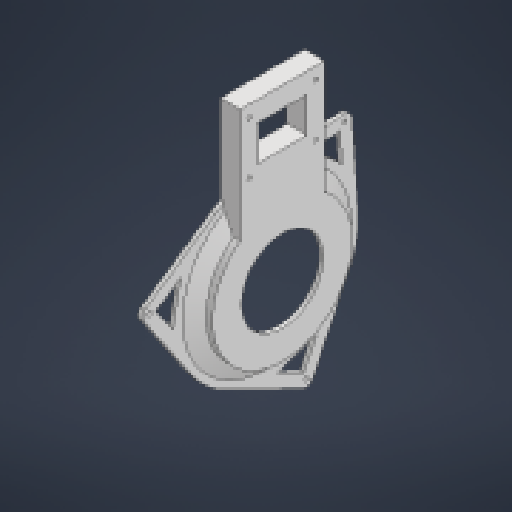
# Autodesk Inventor part: GearCover
Saved by Autodesk Inventor 2027.1 (Build 311270010, 270A)
## iProperties
Created: 2026-11-11
Part Number: GearCover
Material: 一般
Document SubType Name: Modeling
Designer: takuya
Density: 1 g/cm^3
Appearance: 既定
Author: takuya
Autodesk Inventor part; units mm, degrees
ref_plane "作業平面1" through (-57.527, 0, 0) normal (0, 0, 1) x (1, 0, 0)
sketch "スケッチ1" plane through (-57.527, 0, 0) normal (0, 0, 1) x (1, 0, 0)
  line L0 (49.9135, 26.8347) -> (49.9135, 126.8347) projected
  line L1 (35.6909, 64.8149) -> (35.6909, 53.8072) projected
  line L2 (45.137, 49.6849) -> (35.6909, 64.8149)
  line L3 (49.9135, 29.1608) -> (46.9135, 29.1608)
  line L4 (46.9135, 29.1608) -> (35.6909, 53.8072)
  line L5 (49.9135, 29.1608) -> (45.137, 49.6849)
  line L6 (31.3237, 0) -> (61.8943, 0) projected
  point P0 (57.527, 0)
  dimension "d0" = 3
  constraints: 8 end point, 1 horizontal, 1 point on line
  measures "d0" distance of L3.start L3.end
revolve "回転1" add sketch "スケッチ1" angle 360 about axis through (-10, 0, 0) along (1, 0, 0)
sketch "スケッチ2" plane through (-21.8361, 0, 0) normal (-1, 0, 0) x (0, 0, 1)
  line L0 (-32.4955, -82.426) -> (-58.582, -28.1628) projected
  line L1 (-35.518, -56.4528) -> (-26.3428, -75.5385) projected
  arc A0 (-32.4955, -82.426) -> (-25.8072, -84.7584) centre (-27.9892, -80.2596) ccw projected
  circle A1 centre (-27.9892, -80.2596) radius 1.5 projected
  line L2 (-7.2889, -66.2972) -> (-35.518, -56.4528) projected
  line L3 (-26.3428, -75.5385) -> (-7.2889, -66.2972) projected
  line L4 (28.3654, -58.4842) -> (-25.8072, -84.7584) projected
  line L5 (-64.8315, 4.677) -> (-60.4993, 64.7289) projected
  arc A2 (-55.1353, 69.3549) -> (-60.4993, 64.7289) centre (-55.5123, 64.3691) ccw projected
  circle A3 centre (-55.5123, 64.3691) radius 1.5 projected
  line L6 (-52.2469, 60.5827) -> (-53.7706, 39.461) projected
  line L7 (-53.7706, 39.461) -> (-31.1305, 58.9859) projected
  line L8 (-31.1305, 58.9859) -> (-52.2469, 60.5827) projected
  line L9 (-55.1353, 69.3549) -> (4.9013, 64.8149) projected
  line L10 (78.5896, 14.9557) -> (61.0595, 26.8362) projected
  line L11 (66.6486, -2.5331) -> (78.5896, 14.9557) projected
  line L12 (61.0595, 26.8362) -> (66.6486, -2.5331) projected
  circle A4 centre (83.5015, 15.8905) radius 1.5 projected
  arc A5 (87.6307, 13.0711) -> (86.3065, 20.0295) centre (83.5015, 15.8905) ccw projected
  line L13 (36.4662, 53.8072) -> (86.3065, 20.0295) projected
  line L14 (87.6307, 13.0711) -> (53.6807, -36.6521) projected
  arc A6 (-64.8315, 4.677) -> (-58.582, -28.1628) centre (0, 0) ccw projected
  arc A7 (36.4662, 53.8072) -> (4.9013, 64.8149) centre (0, 0) ccw projected
  arc A8 (28.3654, -58.4842) -> (53.6807, -36.6521) centre (0, 0) ccw projected
  circle A9 centre (0, 0) radius 64.8149 projected
  circle A10 centre (0, 0) radius 60
  point P0 (0, 0)
  dimension "d2" = 120
  constraints: 1 centre point, 1 coincident
  measures "d2" diameter of A10
extrude "押し出し1" add sketch "スケッチ2" against normal blind 3 contours L0 A6 L5 A2 L9 A7 L13 A5 L14 A8 L4 A0 | A9
ref_plane "作業平面3" through (-8.0199, 25.6061, 28.2776) normal (-0.0101, -0.0315, 0.9995) x (0.9999, -0.0002, 0.0101)
ref_plane "作業平面4" through (-7.6135, 80.3865, 20) normal (-1, 0, 0) x (0, 0, 1)
sketch "スケッチ6" plane through (-7.6135, 80.3865, 20) normal (-1, 0, 0) x (0, 0, 1)
  circle A0 centre (-43.5, 31.5) radius 1.5 projected
  circle A1 centre (-43.5, -5.5) radius 1.5 projected
  line L0 (-40, 47) -> (-40, 50) projected
  line L1 (-40, 50) -> (-50, 50) projected
  line L2 (-50, -50) -> (-50, 50) projected
  line L3 (-40, -50) -> (-50, -50) projected
  line L4 (-40, -50) -> (-40, -47) projected
  line L5 (-40, -47) -> (-33, -47) projected
  line L6 (-33, -47) -> (-33, -40) projected
  line L7 (-33, -40) -> (-40, -40) projected
  line L8 (-40, -40) -> (-40, 40) projected
  line L9 (-40, 40) -> (-33, 40) projected
  line L10 (-33, 40) -> (-33, 47) projected
  line L11 (-33, 47) -> (-40, 47) projected
  circle A2 centre (3.5, 31.5) radius 1.5 projected
  circle A3 centre (3.5, -5.5) radius 1.5 projected
  line L12 (0, 47) -> (0, 50) projected
  line L13 (-7, 47) -> (0, 47) projected
  line L14 (-7, 40) -> (-7, 47) projected
  line L15 (0, 40) -> (-7, 40) projected
  line L16 (0, -40) -> (0, 40) projected
  line L17 (-7, -40) -> (0, -40) projected
  line L18 (-7, -47) -> (-7, -40) projected
  line L19 (0, -47) -> (-7, -47) projected
  line L20 (0, -50) -> (0, -47) projected
  line L21 (0, -50) -> (10, -50) projected
  line L22 (10, -50) -> (10, 50) projected
  line L23 (0, 50) -> (10, 50) projected
  line L24 (-40, -47) -> (10, -47)
  line L25 (0, 40) -> (-50, 40)
  line L26 (10, -47) -> (-50, -47)
  line L27 (-50, -47) -> (-50, 40)
  line L28 (-50, 40) -> (10, 40)
  line L29 (10, 40) -> (10, -47)
  point P0 (-20, -80.3865)
  point P1 (-7, -47)
  point P2 (0, -47)
  point P3 (10, 40)
  point P4 (0, 40)
  point P5 (-7, 40)
  point P6 (-33, 40)
  point P7 (-40, 40)
  point P8 (-50, -47)
  point P9 (-40, -47)
  point P10 (-33, -47)
  constraints: 12 end point, 3 perpendicular, 2 parallel, 2 point on line, 1 horizontal
extrude "押し出し3" add sketch "スケッチ6" along normal up to surface (14.2226 mm away) contours L25 L15 L16 L17 L18 L24 L6 L7 L8 L9 | L25 L8 L7 L6 L5 L26 L2 | L28 L22 L24 L19 L18 L17 L16
sketch "スケッチ7" plane through (-57.527, 0, 0) normal (0, 0, 1) x (1, 0, 0)
  line L0 (46.9135, -29.1608) -> (35.6909, -53.8072) projected
  line L1 (35.6909, 44.6679) -> (35.6909, 44.6679) projected
  line L2 (46.9135, -29.1608) -> (46.9135, 29.1608) projected
  line L3 (35.6909, -53.8072) -> (35.6909, 44.6679) projected
  line L4 (46.9135, 0) -> (35.6909, 0)
  line L5 (35.6909, 0) -> (35.6909, -53.8072)
  line L6 (35.6909, -53.8072) -> (46.9135, -53.8072)
  line L7 (46.9135, -53.8072) -> (46.9135, 0)
  line L8 (31.2731, 0) -> (61.9027, 0) projected
  point P0 (57.527, 0)
  point P1 (39.7536, 33.3865)
  point P2 (39.7536, 33.3865)
  constraints: 8 end point, 2 parallel, 1 horizontal, 1 midpoint, 1 perpendicular, 1 vertical alignment, 2 other
revolve "回転2" cut sketch "スケッチ7" angle 360 about axis through (-10, 0, 0) along (1, 0, 0) contours L0 L3 L4 L2
sketch "スケッチ8" plane through (-57.527, 0, 0) normal (0, 0, 1) x (1, 0, 0)
  line L0 (49.9135, 33.3865) -> (46.2541, 33.3865) projected
  line L1 (49.9135, -126.3888) -> (49.9135, 161.5157) projected
  line L2 (46.9135, -29.1608) -> (46.9135, 29.1608) projected
  line L3 (46.9135, 29.1608) -> (46.2541, 33.3865)
  line L4 (49.9135, 29.1608) -> (46.9135, 29.1608) projected
  line L5 (48.9301, 33.3865) -> (49.9135, 29.1608) projected
  line L6 (45.137, -49.6849) -> (49.9135, -29.1608) projected
  line L7 (45.137, -49.6849) -> (49.9135, -49.6849)
  line L8 (31.3237, 0) -> (61.8943, 0) projected
  point P0 (57.527, 0)
  constraints: 4 end point, 1 perpendicular, 1 point on line
revolve "回転3" add sketch "スケッチ8" angle 360 about axis through (-10, 0, 0) along (1, 0, 0) contours L1 L7 L6
sketch "スケッチ9" plane through (-7.6135, 80.3865, 20) normal (1, 0, 0) x (0, 0, -1)
  circle A0 centre (20, -80.3865) radius 29.1608 projected
  circle A1 centre (-3.5, -5.5) radius 1.5 projected
  circle A2 centre (-3.5, 31.5) radius 1.5 projected
  circle A3 centre (43.5, 31.5) radius 1.5 projected
  circle A4 centre (43.5, -5.5) radius 1.5 projected
  arc A5 (-10, -40.781) -> (50, -40.781) centre (20, -80.3865) ccw projected
  line L0 (50, 40) -> (50, -40.781) projected
  line L1 (-10, 40) -> (50, 40) projected
  line L2 (-10, -40.781) -> (-10, 40) projected
  line L3 (-10, 40) -> (50, 40)
  line L4 (50, 40) -> (50, -14)
  line L5 (50, -14) -> (-10, -14)
  line L6 (-10, -14) -> (-10, 40)
  line L7 (-3.5, -5.5) -> (43.5, -5.5)
  line L8 (43.5, -5.5) -> (43.5, 31.5)
  line L9 (43.5, 31.5) -> (-3.5, 31.5)
  line L10 (-3.5, 31.5) -> (-3.5, -5.5)
  line L11 (2.5, 0.5) -> (37.5, 0.5)
  line L12 (37.5, 0.5) -> (37.5, 25.5)
  line L13 (37.5, 25.5) -> (2.5, 25.5)
  line L14 (2.5, 25.5) -> (2.5, 0.5)
  point P0 (20, -80.3865)
  point P1 (-3.5, 13)
  point P2 (-10, 13)
  point P3 (2.5, 13)
  point P4 (20, 25.5)
  point P5 (20, 31.5)
  dimension "d11" = 25
  dimension "d12" = 35
  constraints: 24 end point, 6 parallel, 5 midpoint, 3 horizontal, 3 perpendicular, 2 horizontal alignment, 1 point on line, 1 vertical alignment
  measures "d11" distance of L13.end L11.start
  measures "d12" distance of L12.end L13.end
extrude "押し出し4" cut sketch "スケッチ9" against normal up to surface (14.2226 mm away) contours L14 L13 L12 L11
sketch "スケッチ11" plane through (-57.527, 0, 0) normal (0, 0, 1) x (1, 0, 0)
  line L0 (38.6909, -60.0098) -> (45.137, -49.6849) projected
  line L1 (38.6909, -60.0098) -> (35.6909, -60.0098)
  line L2 (35.6909, -82.426) -> (35.6909, -28.1628) projected
  line L3 (35.6909, -60.0098) -> (42.137, -49.6849)
  line L4 (42.137, -49.6849) -> (45.137, -49.6849)
  line L5 (49.9135, -49.6849) -> (45.137, -49.6849) projected
  line L6 (46.9135, -29.1608) -> (46.9135, 29.1608) projected
  line L7 (42.137, -49.6849) -> (46.9135, -29.1608)
  line L8 (46.9135, -29.1608) -> (35.6909, -53.8072) projected
  line L9 (35.6909, -82.426) -> (35.6909, -28.1628) projected
  line L10 (31.3237, 0) -> (61.8943, 0) projected
  point P0 (57.527, 0)
  constraints: 8 end point, 1 collinear, 1 horizontal, 1 parallel, 1 point on line
revolve "回転4" cut sketch "スケッチ11" angle 360 about axis through (-10, 0, 0) along (1, 0, 0) contours L2 L8 L7 L3
